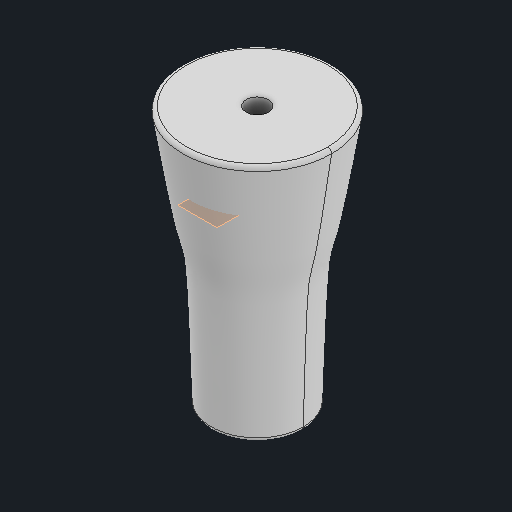
# Autodesk Inventor part: leg-tissue
Saved by Autodesk Inventor 2026.2 (Build 302298010, 298A)
## iProperties
Created: 2026-10-22
Part Number: leg-tissue
Material: Generic
Document SubType Name: Modeling
Designer: user
Density: 1 g/cm^3
Appearance: Default
Mass: 6268.59 g
Surface Area: 2413.06 cm^2
Volume: 6268.59 cm^3
Author: user
Autodesk Inventor part; units mm, degrees
ref_plane "YZ Plane" through (0, 0, 0) normal (1, 0, 0) x (0, 1, 0)
sketch "Sketch1" plane through (0, 0, 0) normal (0, 0, 1) x (1, 0, 0)
  line L0 (0, 0) -> (48.2, 0)
  line L1 (48.2, 0) -> (48.2, 230)
  line L2 (48.2, 230) -> (0, 230)
  line L3 (0, 230) -> (0, 0)
  dimension "d0" = 48.2
  dimension "d1" = 230
  constraints: 8 end point, 2 parallel, 1 horizontal, 1 perpendicular
  measures "d0" distance of L0.start L0.end
  measures "d1" distance of L2.end L0.start
extrude "Extrusion1" [suppressed]
ref_plane "Knee line 115" through (0, 115, 0) normal (0, 1, 0) x (-1, 0, 0)
split "Split1" [suppressed]
sketch "S7_leg" plane through (0, 0, 0) normal (0, 0, 1) x (1, 0, 0)
  spline S0 degree 4 poles (62, -170) (62.0086, -169.6862) (62.0259, -169.0586) (62.0518, -168.1172) (62.0867, -166.862) (62.1218, -165.6068) (62.1571, -164.3516) (62.1927, -163.0964) (62.2284, -161.8412) (62.2644, -160.586) (62.3007, -159.3308) (62.3372, -158.0756) (62.3739, -156.8205) (62.4109, -155.5653) (62.4482, -154.3101) (62.4857, -153.0549) (62.5234, -151.7998) (62.5615, -150.5446) (62.5998, -149.2894) (62.6383, -148.0343) (62.6772, -146.7791) (62.7163, -145.524) (62.7557, -144.2688) (62.7954, -143.0137) (62.8353, -141.7585) (62.8756, -140.5034) (62.9161, -139.2483) (62.957, -137.9931) (62.9981, -136.738) (63.0396, -135.4829) (63.0814, -134.2278) (63.1235, -132.9727) (63.1659, -131.7175) (63.2086, -130.4624) (63.2516, -129.2073) (63.2949, -127.9522) (63.3385, -126.6971) (63.3826, -125.442) (63.4271, -124.187) (63.4719, -122.9319) (63.5171, -121.6768) (63.5623, -120.4217) (63.6075, -119.1666) (63.6526, -117.9116) (63.6974, -116.6565) (63.7418, -115.4014) (63.7858, -114.1463) (63.8293, -112.8911) (63.8724, -111.636) (63.9151, -110.3809) (63.9575, -109.1257) (63.9997, -107.8706) (64.0417, -106.6154) (64.0834, -105.3602) (64.1249, -104.1051) (64.1662, -102.8499) (64.2073, -101.5947) (64.2482, -100.3395) (64.2891, -99.0843) (64.3298, -97.8292) (64.3705, -96.574) (64.4111, -95.3188) (64.4516, -94.0636) (64.4922, -92.8083) (64.5327, -91.5531) (64.5733, -90.2979) (64.614, -89.0427) (64.6547, -87.7875) (64.6956, -86.5323) (64.7365, -85.2771) (64.7776, -84.0219) (64.8189, -82.7666) (64.8604, -81.5114) (64.9021, -80.2562) (64.944, -79.001) (64.9862, -77.7458) (65.0286, -76.4906) (65.0714, -75.2354) (65.1145, -73.9802) (65.158, -72.725) (65.2018, -71.4698) (65.2461, -70.2146) (65.2907, -68.9594) (65.3358, -67.7042) (65.3814, -66.4491) (65.4274, -65.1939) (65.474, -63.9387) (65.5211, -62.6836) (65.5688, -61.4284) (65.617, -60.1733) (65.6659, -58.9182) (65.7153, -57.6631) (65.7654, -56.4079) (65.8162, -55.1529) (65.8677, -53.8978) (65.9199, -52.6427) (65.9728, -51.3876) (66.0265, -50.1326) (66.081, -48.8776) (66.1363, -47.6225) (66.1924, -46.3675) (66.2494, -45.1125) (66.3072, -43.8576) (66.366, -42.6026) (66.4256, -41.3477) (66.4862, -40.0928) (66.5478, -38.8379) (66.6104, -37.583) (66.6739, -36.3282) (66.7385, -35.0734) (66.8042, -33.8186) (66.8709, -32.5638) (66.9387, -31.3091) (67.0077, -30.0544) (67.0779, -28.7997) (67.1492, -27.545) (67.2216, -26.2904) (67.2953, -25.0358) (67.3701, -23.7813) (67.4462, -22.5267) (67.5236, -21.2723) (67.6025, -20.0178) (67.6828, -18.7634) (67.7644, -17.5091) (67.8472, -16.2547) (67.9311, -15.0005) (68.0162, -13.7462) (68.1029, -12.492) (68.1915, -11.2379) (68.2822, -9.9838) (68.3748, -8.7298) (68.4688, -7.4759) (68.5632, -6.222) (68.6577, -4.9681) (68.7526, -3.7142) (68.8492, -2.4603) (68.9498, -1.2066) (69.057, 0.0468) (69.1737, 1.2999) (69.3023, 2.5524) (69.4447, 3.8041) (69.6022, 5.055) (69.7754, 6.3048) (69.9636, 7.5536) (70.1656, 8.8013) (70.38, 10.048) (70.6054, 11.2938) (70.8411, 12.5386) (71.0864, 13.7825) (71.3411, 15.0254) (71.6046, 16.2675) (71.8764, 17.5087) (72.1558, 18.7491) (72.4418, 19.9888) (72.7338, 21.2278) (73.0311, 22.4661) (73.3329, 23.704) (73.6387, 24.9413) (73.9479, 26.1783) (74.2599, 27.4149) (74.5741, 28.6513) (74.8897, 29.8875) (75.2062, 31.1235) (75.5228, 32.3596) (75.8387, 33.5957) (76.1534, 34.832) (76.4663, 36.0685) (76.7767, 37.3053) (77.0842, 38.5425) (77.3883, 39.7801) (77.6883, 41.0181) (77.9832, 42.2568) (78.2719, 43.4961) (78.5535, 44.7362) (78.8274, 45.9772) (79.0933, 47.219) (79.3517, 48.4616) (79.6032, 49.7048) (79.8491, 50.9487) (80.0907, 52.1929) (80.3295, 53.4373) (80.5669, 54.6819) (80.8038, 55.9265) (81.0406, 57.1712) (81.277, 58.4158) (81.5127, 59.6606) (81.7472, 60.9054) (81.9804, 62.1504) (82.2123, 63.3955) (82.4431, 64.6406) (82.6732, 65.8859) (82.9024, 67.1312) (83.131, 68.3766) (83.3587, 69.622) (83.5855, 70.8675) (83.8115, 72.1131) (84.0366, 73.3588) (84.2609, 74.6045) (84.4844, 75.8503) (84.7072, 77.0962) (84.9292, 78.3421) (85.1506, 79.5881) (85.3713, 80.8341) (85.5912, 82.0802) (85.8105, 83.3264) (86.0292, 84.5726) (86.2473, 85.8188) (86.4647, 87.0651) (86.6816, 88.3114) (86.8978, 89.5578) (87.1135, 90.8043) (87.3286, 92.0507) (87.5433, 93.2973) (87.7575, 94.5438) (87.9713, 95.7904) (88.1847, 97.037) (88.3976, 98.2836) (88.6099, 99.5303) (88.8214, 100.7771) (89.0322, 102.0239) (89.2421, 103.2708) (89.451, 104.5177) (89.6589, 105.7648) (89.8658, 107.0119) (90.0718, 108.2591) (90.2769, 109.5063) (90.4813, 110.7536) (90.6849, 112.001) (90.8878, 113.2484) (91.09, 114.4959) (91.2915, 115.7434) (91.4925, 116.991) (91.6928, 118.2386) (91.8927, 119.4862) (92.092, 120.7339) (92.2909, 121.9816) (92.4894, 123.2293) (92.6875, 124.4771) (92.8853, 125.7249) (93.0828, 126.9727) (93.2801, 128.2205) (93.4771, 129.4683) (93.674, 130.7162) (93.8707, 131.964) (94.0673, 133.2119) (94.2639, 134.4597) (94.4605, 135.7076) (94.6571, 136.9554) (94.8537, 138.2033) (95.0505, 139.4511) (95.2473, 140.6989) (95.4444, 141.9467) (95.6416, 143.1945) (95.8392, 144.4422) (96.0372, 145.6899) (96.2355, 146.9376) (96.4341, 148.1853) (96.633, 149.4329) (96.8322, 150.6805) (97.0315, 151.9281) (97.2309, 153.1757) (97.4302, 154.4233) (97.6294, 155.6709) (97.8285, 156.9185) (98.0275, 158.1662) (98.2263, 159.4138) (98.4252, 160.6614) (98.6239, 161.909) (98.8227, 163.1567) (99.0214, 164.4043) (99.22, 165.6519) (99.4185, 166.8996) (99.617, 168.1472) (99.8154, 169.3949) (100.0138, 170.6425) (100.2121, 171.8902) (100.4104, 173.1378) (100.6086, 174.3855) (100.8068, 175.6332) (101.0049, 176.8808) (101.203, 178.1285) (101.3515, 179.0642) (101.4505, 179.6881) (101.5, 180) knots 0 0 0 0 0 0.003571 0.007143 0.010714 0.014286 0.017857 0.021429 0.025 0.028571 0.032143 0.035714 0.039286 0.042857 0.046429 0.05 0.053571 0.057143 0.060714 0.064286 0.067857 0.071429 0.075 0.078571 0.082143 0.085714 0.089286 0.092857 0.096429 0.1 0.103571 0.107143 0.110714 0.114286 0.117857 0.121429 0.125 0.128571 0.132143 0.135714 0.139286 0.142857 0.146429 0.15 0.153571 0.157143 0.160714 0.164286 0.167857 0.171429 0.175 0.178571 0.182143 0.185714 0.189286 0.192857 0.196429 0.2 0.203571 0.207143 0.210714 0.214286 0.217857 0.221429 0.225 0.228571 0.232143 0.235714 0.239286 0.242857 0.246429 0.25 0.253571 0.257143 0.260714 0.264286 0.267857 0.271429 0.275 0.278571 0.282143 0.285714 0.289286 0.292857 0.296429 0.3 0.303571 0.307143 0.310714 0.314286 0.317857 0.321429 0.325 0.328571 0.332143 0.335714 0.339286 0.342857 0.346429 0.35 0.353571 0.357143 0.360714 0.364286 0.367857 0.371429 0.375 0.378571 0.382143 0.385714 0.389286 0.392857 0.396429 0.4 0.403571 0.407143 0.410714 0.414286 0.417857 0.421429 0.425 0.428571 0.432143 0.435714 0.439286 0.442857 0.446429 0.45 0.453571 0.457143 0.460714 0.464286 0.467857 0.471429 0.475 0.478571 0.482143 0.485714 0.489286 0.492857 0.496429 0.5 0.503571 0.507143 0.510714 0.514286 0.517857 0.521429 0.525 0.528571 0.532143 0.535714 0.539286 0.542857 0.546429 0.55 0.553571 0.557143 0.560714 0.564286 0.567857 0.571429 0.575 0.578571 0.582143 0.585714 0.589286 0.592857 0.596429 0.6 0.603571 0.607143 0.610714 0.614286 0.617857 0.621429 0.625 0.628571 0.632143 0.635714 0.639286 0.642857 0.646429 0.65 0.653571 0.657143 0.660714 0.664286 0.667857 0.671429 0.675 0.678571 0.682143 0.685714 0.689286 0.692857 0.696429 0.7 0.703571 0.707143 0.710714 0.714286 0.717857 0.721429 0.725 0.728571 0.732143 0.735714 0.739286 0.742857 0.746429 0.75 0.753571 0.757143 0.760714 0.764286 0.767857 0.771429 0.775 0.778571 0.782143 0.785714 0.789286 0.792857 0.796429 0.8 0.803571 0.807143 0.810714 0.814286 0.817857 0.821429 0.825 0.828571 0.832143 0.835714 0.839286 0.842857 0.846429 0.85 0.853571 0.857143 0.860714 0.864286 0.867857 0.871429 0.875 0.878571 0.882143 0.885714 0.889286 0.892857 0.896429 0.9 0.903571 0.907143 0.910714 0.914286 0.917857 0.921429 0.925 0.928571 0.932143 0.935714 0.939286 0.942857 0.946429 0.95 0.953571 0.957143 0.960714 0.964286 0.967857 0.971429 0.975 0.978571 0.982143 0.985714 0.989286 0.992857 0.996429 1 1 1 1 1
  line L0 (101.5, 180) -> (0, 180)
  line L1 (0, 180) -> (0, -170)
  line L2 (0, -170) -> (62, -170)
  line L3 (0, -245.1988) -> (0, 256.595) projected
  point P0 (62.1389, -165.0009)
  point P1 (62.2813, -160.0019)
  point P2 (62.4276, -155.0028)
  point P3 (62.578, -150.0037)
  point P4 (62.7326, -145.0045)
  point P5 (62.8917, -140.0054)
  point P6 (63.0555, -135.0062)
  point P7 (63.2242, -130.0069)
  point P8 (63.398, -125.0076)
  point P9 (63.5772, -120.0083)
  point P10 (63.7555, -115.0089)
  point P11 (63.9276, -110.0094)
  point P12 (64.0949, -105.0099)
  point P13 (64.2589, -100.0102)
  point P14 (64.421, -95.0106)
  point P15 (64.5826, -90.0108)
  point P16 (64.7452, -85.011)
  point P17 (64.9103, -80.011)
  point P18 (65.0792, -75.011)
  point P19 (65.2534, -70.0109)
  point P20 (65.4343, -65.0108)
  point P21 (65.6234, -60.0105)
  point P22 (65.8222, -55.0102)
  point P23 (66.032, -50.0098)
  point P24 (66.2543, -45.0094)
  point P25 (66.4905, -40.0088)
  point P26 (66.7421, -35.0082)
  point P27 (67.0105, -30.0075)
  point P28 (67.2972, -25.0068)
  point P29 (67.6036, -20.006)
  point P30 (67.9311, -15.0051)
  point P31 (68.2811, -10.0042)
  point P32 (68.6551, -5.0033)
  point P33 (69.0546, -0.0023)
  point P34 (69.5981, 4.9987)
  point P35 (70.3738, 9.9998)
  point P36 (71.3378, 15.0008)
  point P37 (72.4462, 20.0019)
  point P38 (73.6548, 25.003)
  point P39 (74.9197, 30.004)
  point P40 (76.1969, 35.0051)
  point P41 (77.4425, 40.0061)
  point P42 (78.6123, 45.0071)
  point P43 (79.6625, 50.008)
  point P44 (80.6291, 55.0089)
  point P45 (81.5783, 60.0097)
  point P46 (82.5114, 65.0104)
  point P47 (83.4295, 70.0111)
  point P48 (84.3338, 75.0117)
  point P49 (85.2256, 80.0122)
  point P50 (86.1061, 85.0125)
  point P51 (86.9765, 90.0128)
  point P52 (87.838, 95.013)
  point P53 (88.6917, 100.013)
  point P54 (89.5335, 105.013)
  point P55 (90.3598, 110.0128)
  point P56 (91.1734, 115.0125)
  point P57 (91.9767, 120.0121)
  point P58 (92.7722, 125.0116)
  point P59 (93.5627, 130.0109)
  point P60 (94.3506, 135.0102)
  point P61 (95.1385, 140.0093)
  point P62 (95.9291, 145.0084)
  point P63 (96.7248, 150.0073)
  point P64 (97.5233, 155.0062)
  point P65 (98.3206, 160.0051)
  point P66 (99.1168, 165.0038)
  point P67 (99.912, 170.0026)
  point P68 (100.7064, 175.0013)
  constraints: 6 end point, 71 other
revolve "Leg_revolve_B8_2SD" add sketch "S7_leg" angle 360 about axis through (0, -10, 0) along (0, 1, 0) separate body
ref_plane "Work Plane2" through (0, 10, 0) normal (0, 1, 0) x (0, 0, 1)
sketch "S7_bone_t" plane through (0, 10, 0) normal (0, 1, 0) x (0, 0, 1)
  circle A0 centre (0, 0) radius 15
  constraints: 1 centre point
extrude "Femur_hole_D30" cut sketch "S7_bone_t" along normal blind 200
ref_plane "Work Plane3" through (0, -10, 0) normal (0, -1, 0) x (1, 0, 0)
sketch "S7_bone_s" plane through (0, -10, 0) normal (0, -1, 0) x (1, 0, 0)
  circle A0 centre (0, 0) radius 15
  constraints: 1 centre point
extrude "Tibia_hole_D30" cut sketch "S7_bone_s" along normal blind 200
fillet "Leg_end_R5" radius 5 2 edges at (-62, -170, 0) (-101.5, 180, 0)
body "Solid1"
body "Solid2"
